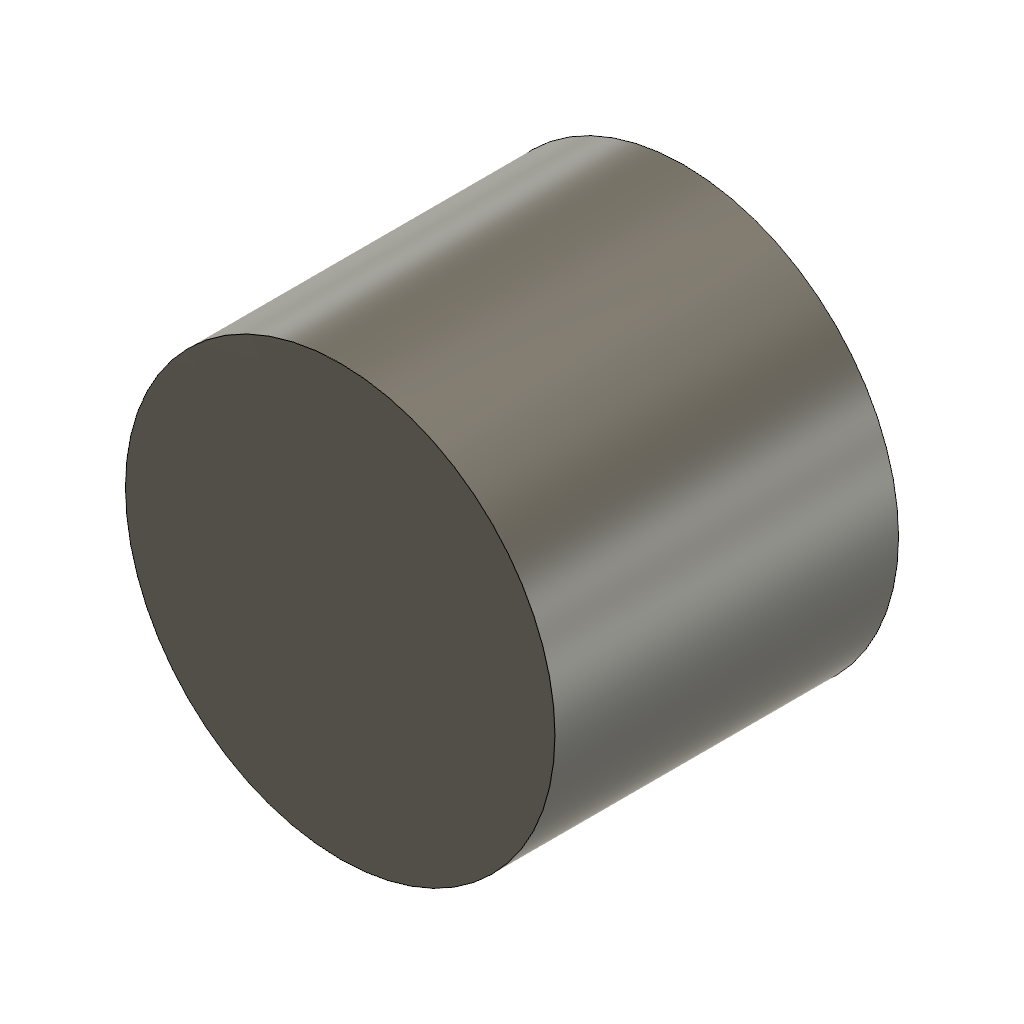
OffsetCylinderProductionPermutedHistory (Autodesk Fusion 360 design; units mm, degrees)
part number: 2026-10-20-20-19-12-129
Autodesk Fusion 360 part; units mm, degrees
sketch "Sketch1" plane through (0, 0, 0) normal (0, 0, 1) x (1, 0, 0)
  circle A0 centre (20, 20) radius 10
extrude "FaceEditSeed" add sketch "Sketch1" along normal blind 20
move_face "ProbeFaceEdit" offset 2.5 1 faces at (29.9876, 19.5015, 13.3333)
